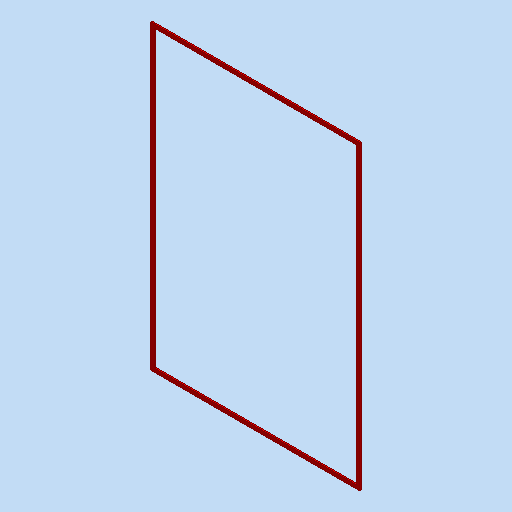
# Autodesk Inventor part: MM0861AN200_G22_313
Saved by Autodesk Inventor 2023.3 (Build 273359000, 359)
## iProperties
Part Number: MM0861AN200_G22_313
Material: Generisch
Description: =<RBPARTNOTITLE2>
Vendor: Häwa
Document SubType Name: Modeling
Designer: Benutzer
Mass: 132.792 g
Surface Area: 905.4 cm^2
Volume: 132.792 cm^3
Density: 1 g/cm^3
Appearance: rot AnP
RBDOCUMENTTYPE: DRF
RBDOCUMENTVERSION: 00
RBDRAWINGMAINSCALE: 1:1
RBDRAWINGMISSINGSPEC: --
RBDRAWINGVOLUME: --
RBGBEDGESIN1: +0,5
RBGBEDGESIN2: +0,2
RBGBEDGESOUT1: -0,3
RBGBEDGESOUT2: -0,1
RBMATERIAL: --
RBMATMEETS: --
RBMATNO: =<Part Number>
RBPARTMADEOF: 3080-0102-18-00 lg= 3500mm
RBPARTNO: SIEHE MNR
RBPARTNOTITLE1: Gummidichtung
RBPARTNOTITLE2: Gummidichtung
RBPARTSAFETYINDICATOR: --
RBSURFACE: --
RBSURFACE2: --
RBZEDGESNORM: ISO13715:2002-06
RBZGENDIMCLASS: m
RBZGENDIMNORM: ISO 2768-1:1989-11
RBZGENGEOCLASS: H
RBZGENGEONORM: ISO 2768-2:1989-11
RBZSURFACENORM: ISO13D2:2002-02
RBZTOLERANCENORM: ISO 14405-1:2010-12
AnP_Material: =<Material>
AnP_TemplVers: 20190222
AnP_Kategorie: 2
MaxAbmaße: 800 x 4 x 11 (FM)
Author: Benutzer
Keywords: =<RBPARTMADEOF>
Comments: =<RBSURFACE2>
Revision Number: 01
Autodesk Inventor part; units mm, degrees
ref_plane "YZ Plane" through (0, 0, 0) normal (1, 0, 0) x (0, 1, 0)
ref_plane "XZ Plane" through (0, 0, 0) normal (0, 1, 0) x (-1, 0, 0)
ref_plane "XY Plane" through (0, 0, 0) normal (0, 0, 1) x (1, 0, 0)
sketch "Skizze1" plane through (0, 0, 0) normal (0, 0, 1) x (1, 0, 0)
  line L0 (0, 0) -> (11, 0)
  line L1 (11, 0) -> (11, 4)
  line L2 (11, 4) -> (0, 4)
  line L3 (0, 4) -> (0, 0)
  dimension "d0" = 11
  dimension "d1" = 4
  constraints: 8 end point, 2 parallel, 1 horizontal, 1 perpendicular
  measures "d0" distance of L2.end L1.end
  measures "d1" distance of L1.end L0.end
extrude "Extrusion1" add sketch "Skizze1" along normal blind 905
sketch "Skizze2" plane through (11, 4, 905) normal (1, 0, 0) x (0, 0, -1)
  line L0 (905, -4) -> (905, 0) projected
  line L1 (905, 0) -> (0, 0) projected
  line L2 (0, -4) -> (0, 0) projected
  line L3 (905, -4) -> (0, -4) projected
  line L4 (0, -4) -> (11, -4)
  line L5 (11, -4) -> (11, 0)
  line L6 (11, 0) -> (0, 0)
  line L7 (0, 0) -> (0, -4)
  line L8 (905, 0) -> (894, 0)
  line L9 (894, 0) -> (894, -4)
  line L10 (894, -4) -> (905, -4)
  line L11 (905, -4) -> (905, 0)
  dimension "d4" = 11
  constraints: 16 end point, 4 parallel, 2 horizontal, 2 perpendicular, 1 point on line
  measures "d4" distance of L10.end L9.end
extrude "Extrusion2" add sketch "Skizze2" along normal blind 615 contours L3 L9 L1 L0 | L3 L2 L1 L5
sketch "Skizze3" plane through (11, 0, 11) normal (0, 0, 1) x (1, 0, 0)
  line L0 (-11, 0) -> (615, 0) projected
  line L1 (615, 4) -> (615, 0) projected
  line L2 (-11, 4) -> (615, 4) projected
  line L3 (-11, 4) -> (-11, 0) projected
  line L4 (615, 4) -> (604, 4)
  line L5 (604, 4) -> (604, 0)
  line L6 (604, 0) -> (615, 0)
  line L7 (615, 0) -> (615, 4)
  dimension "d7" = 11
  constraints: 8 end point, 2 parallel, 1 horizontal, 1 perpendicular, 1 point on line
  measures "d7" distance between parallel lines of L1 L5
extrude "Extrusion3" add sketch "Skizze3" along normal up to next contours L5 L2 L1 L0
